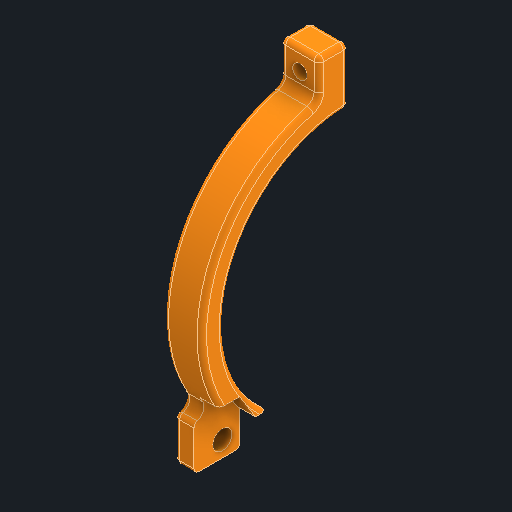
# Autodesk Inventor part: ra_wrap_strap_pz
Saved by Autodesk Inventor 2027.1 (Build 311270010, 270A)
## iProperties
Created: 2026-11-04
Part Number: ra_wrap_strap_pz
Material: Generic
Description: RA wrap strap +Z half: wraps over the RA body, lug on the flat bit +Z axial M5 (M5x25), M4x16 top joint; print PETG/ASA
Document SubType Name: Modeling
Designer: Claude (from photos)
Density: 1 g/cm^3
Appearance: Orange
Author: alexg
Autodesk Inventor part; units mm, degrees
ref_plane "Work Plane1" through (1, 0, 0) normal (1, 0, 0) x (0, 1, 0)
sketch "Band sketch" plane through (1, 0, 0) normal (1, 0, 0) x (0, 1, 0)
  circle A0 centre (0, 0) radius 47
  constraints: 1 centre point
extrude "Band" add sketch "Band sketch" along normal blind 12
ref_plane "Work Plane2" through (1, 0, 0) normal (1, 0, 0) x (0, 1, 0)
sketch "Keep this half sketch" plane through (1, 0, 0) normal (1, 0, 0) x (0, 1, 0)
  line L0 (-60, -60) -> (60, -60)
  line L1 (60, -60) -> (60, 0.75)
  line L2 (60, 0.75) -> (-60, 0.75)
  line L3 (-60, 0.75) -> (-60, -60)
  constraints: 8 end point, 2 parallel, 1 horizontal, 1 perpendicular
extrude "Keep this half" cut sketch "Keep this half sketch" along normal blind 12
ref_plane "Work Plane3" through (1, 0, 0) normal (1, 0, 0) x (0, 1, 0)
sketch "Open below the RA body (latitude pivot web) sketch" plane through (1, 0, 0) normal (1, 0, 0) x (0, 1, 0)
  line L0 (-60, -60) -> (-30, -60)
  line L1 (-30, -60) -> (-30, 60)
  line L2 (-30, 60) -> (-60, 60)
  line L3 (-60, 60) -> (-60, -60)
  constraints: 8 end point, 2 parallel, 1 horizontal, 1 perpendicular
extrude "Open below the RA body (latitude pivot web)" cut sketch "Open below the RA body (latitude pivot web) sketch" along normal blind 12
ref_plane "Work Plane4" through (1, 0, 0) normal (1, 0, 0) x (0, 1, 0)
sketch "Lug on the flat bit axial M5 sketch" plane through (1, 0, 0) normal (1, 0, 0) x (0, 1, 0)
  line L0 (-42, 29) -> (-28, 29)
  line L1 (-28, 29) -> (-28, 43.5)
  line L2 (-28, 43.5) -> (-42, 43.5)
  line L3 (-42, 43.5) -> (-42, 29)
  constraints: 8 end point, 2 parallel, 1 horizontal, 1 perpendicular
extrude "Lug on the flat bit axial M5" add sketch "Lug on the flat bit axial M5 sketch" along normal blind 12
ref_plane "Work Plane5" through (1, 0, 0) normal (1, 0, 0) x (0, 1, 0)
sketch "Top clamp ear sketch" plane through (1, 0, 0) normal (1, 0, 0) x (0, 1, 0)
  line L0 (42, 0.75) -> (58, 0.75)
  line L1 (58, 0.75) -> (58, 10)
  line L2 (58, 10) -> (42, 10)
  line L3 (42, 10) -> (42, 0.75)
  constraints: 8 end point, 2 parallel, 1 horizontal, 1 perpendicular
extrude "Top clamp ear" add sketch "Top clamp ear sketch" along normal blind 12
ref_plane "Work Plane6" through (1, 0, 0) normal (1, 0, 0) x (0, 1, 0)
sketch "RA body bore sketch" plane through (1, 0, 0) normal (1, 0, 0) x (0, 1, 0)
  circle A0 centre (0, 0) radius 40
  constraints: 1 centre point
extrude "RA body bore" cut sketch "RA body bore sketch" along normal blind 12
ref_plane "Work Plane7" through (7, 0, 0) normal (1, 0, 0) x (0, 1, 0)
sketch "Seat for the bracket tab (stacks under the strap) sketch" plane through (7, 0, 0) normal (1, 0, 0) x (0, 1, 0)
  line L0 (-42, 29) -> (-42, 44.5)
  line L1 (-42, 44.5) -> (-22, 44.5)
  line L2 (-22, 44.5) -> (-22, 35)
  line L3 (-22, 35) -> (-30, 30)
  line L4 (-30, 30) -> (-30, 29)
  line L5 (-30, 29) -> (-42, 29)
  constraints: 12 end point
extrude "Seat for the bracket tab (stacks under the strap)" cut sketch "Seat for the bracket tab (stacks under the strap) sketch" along normal blind 6
ref_plane "Work Plane8" through (1, 0, 0) normal (1, 0, 0) x (0, 1, 0)
sketch "M5 hole (6 mm) sketch" plane through (1, 0, 0) normal (1, 0, 0) x (0, 1, 0)
  circle A0 centre (-37, 34.5) radius 3
  constraints: 1 centre point
extrude "M5 hole (6 mm)" cut sketch "M5 hole (6 mm) sketch" along normal blind 12
sketch "M4 clearance (top joint) sketch" plane through (0, 0, 0) normal (0, 0, 1) x (1, 0, 0)
  circle A0 centre (7, 51.5) radius 2.25
  constraints: 1 centre point
extrude "M4 clearance (top joint)" cut sketch "M4 clearance (top joint) sketch" along normal blind 12
fillet "Fillets (inside corners) R3 (2 edges)" radius 3 2 edges at (4, -28, 37.7492) (7, 45.9239, 10)
fillet "Rounds (outside edges) R1.5 (19 edges)" radius 1.5 19 edges at (4, -42, 43.5) (1, -42, 36.25) (4, -42, 29) (4, -28, 43.5) (1, -35, 43.5) (13, 18.7487, 43.0986) (1, 17.9596, 43.4333) (1, 13.7907, 37.5475) (7, 39.993, 0.75) (13, 13.7907, 37.5475) (13, 48.9965, 0.75) (13, 58, 5.375) (13, 53.1402, 10) (7, 58, 10) (1, 53.1402, 10) (1, 58, 5.375) (7, 58, 0.75) (1, 48.9965, 0.75) (1, -36, 29)
body "Solid1"
